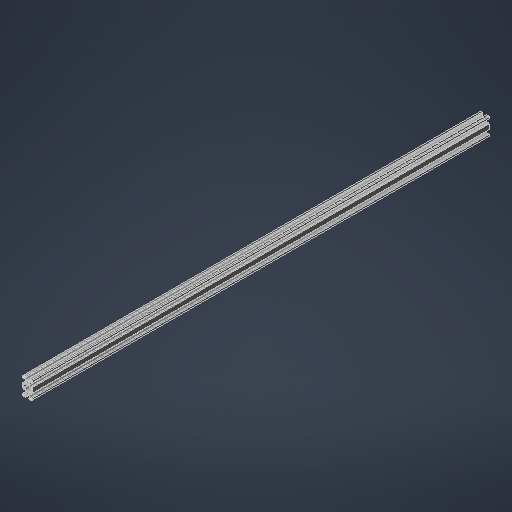
# Autodesk Inventor part: 2040aluminum_extrusion_black
Saved by Autodesk Inventor 2027.1 (Build 311270010, 270A)
## iProperties
Created: 2021-10-28
Part Number: 2040aluminum_extrusion_black
Material: Aluminum 6061
Document SubType Name: Modeling
Designer: casper
Density: 2.7 g/cm^3
Appearance: Satin - Black
Author: casper
Autodesk Inventor part; units mm, degrees
ref_plane "YZ Plane" through (0, 0, 0) normal (1, 0, 0) x (0, 1, 0)
ref_plane "XZ Plane" through (0, 0, 0) normal (0, 1, 0) x (-1, 0, 0)
sketch "Sketch1" plane through (0, 0, 0) normal (0, 0, 1) x (1, 0, 0)
  line L0 (0, 3.7) -> (-2.6393, 3.7)
  line L1 (-2.6393, 3.7) -> (-5.5, 6.5607)
  line L2 (-5.5, 6.5607) -> (-5.5, 8.2)
  line L3 (-5.5, 8.2) -> (-3.395, 8.2)
  line L4 (-3.395, 8.2) -> (-3.395, 10)
  line L5 (-3.395, 10) -> (-10, 10)
  line L6 (-10, 10) -> (-10, 3.395)
  line L7 (-10, 3.395) -> (-8.2, 3.395)
  line L8 (-8.2, 3.395) -> (-8.2, 5.5)
  line L9 (-8.2, 5.5) -> (-6.5607, 5.5)
  line L10 (-6.5607, 5.5) -> (-3.7, 2.6393)
  line L11 (-3.7, 2.6393) -> (-3.7, 0)
  line L12 (0, 0) -> (-10, 10) construction
  circle A0 centre (0, 0) radius 2.3
  line L13 (-22.6601, 0) -> (65.9605, 0) projected
  line L14 (-3.7, 0) -> (0, 0)
  line L15 (0, 0) -> (0, 3.7)
  line L16 (11.2521, 18.9743) -> (53.3004, 18.9743) construction
  line L17 (53.3004, 18.9743) -> (53.3004, -5.624) construction
  line L18 (53.3004, -5.624) -> (11.2521, -5.624) construction
  line L19 (11.2521, -5.624) -> (11.2521, 18.9743) construction
  point P0 (-2.3, 0)
  point P1 (0, 2.3)
  dimension "d0" = 1.5
  dimension "d6" = 6.3
  dimension "d9" = 4.6
  dimension "d18" = 135
  dimension "d22" = 20
  dimension "d34" = 11
  dimension "d35" = 6.79
  dimension "d36" = 1.8
  constraints: 30 end point, 6 equal length, 6 perpendicular, 2 horizontal, 2 parallel, 2 vertical, 1 centre point, 1 coincident, 2 other
  measures "d0" distance between parallel lines of L1 L10
  measures "d6" distance between parallel lines of L0 L5
  measures "d9" diameter of A0
  measures "d18" angle of L13 L12
  measures "d22" diameter of L5 L14
  measures "d34" diameter of L2 L15
  measures "d35" diameter of L4 L15
  measures "d36" distance between parallel lines of L5 L3
extrude "Extrusion1" add sketch "Sketch1" along normal mid plane 1000 contours L15 A0 L13 L11 L10 L9 L8 L7 L6 L5 L4 L3 L2 L1 L0
pattern_circular "Circular Pattern1" count 4 over 360 about axis through (0, 0, -10) along (0, 0, 1) of "Extrusion1"
chamfer "Chamfer1" distance 1.185 angle 45 8 edges at (-3.395, 10, 0) (3.395, 10, 0) (10, 3.395, 0) (10, -3.395, 0) (3.395, -10, 0) (-3.395, -10, 0) (-10, -3.395, 0) (-10, 3.395, 0)
ref_plane "Work Plane1" through (4.58, 10, 500) normal (0, 1, 0) x (1, 0, 0)
mirror "Mirror1" about plane through (4.58, 10, 500) normal (0, 1, 0)
sketch "Sketch2" plane through (0, 0, 500) normal (0, 0, 1) x (1, 0, 0)
  line L0 (-10, 4.58) -> (-10, 15.42) projected
  line L1 (-8.815, 3.395) -> (-10, 4.58) projected
  line L2 (-8.815, 3.395) -> (-8.2, 3.395) projected
  line L3 (-8.2, 3.395) -> (-8.2, 5.5) projected
  line L4 (-8.2, 5.5) -> (-6.5607, 5.5) projected
  line L5 (-6.5607, 5.5) -> (-3.7, 2.6393) projected
  line L6 (-3.7, 2.6393) -> (-3.7, 0) projected
  line L7 (-3.7, 0) -> (-3.7, -2.6393) projected
  line L8 (-3.7, -2.6393) -> (-6.5607, -5.5) projected
  line L9 (-6.5607, -5.5) -> (-8.2, -5.5) projected
  line L10 (-8.2, -5.5) -> (-8.2, -3.395) projected
  line L11 (-8.2, -3.395) -> (-8.815, -3.395) projected
  line L12 (-10, -4.58) -> (-8.815, -3.395) projected
  line L13 (-10, -4.58) -> (-10, -10) projected
  line L14 (-10, -10) -> (-4.58, -10) projected
  line L15 (-3.395, -8.815) -> (-4.58, -10) projected
  line L16 (-3.395, -8.815) -> (-3.395, -8.2) projected
  line L17 (-3.395, -8.2) -> (-5.5, -8.2) projected
  line L18 (-5.5, -8.2) -> (-5.5, -6.5607) projected
  line L19 (-5.5, -6.5607) -> (-2.6393, -3.7) projected
  line L20 (-2.6393, -3.7) -> (0, -3.7) projected
  line L21 (0, -3.7) -> (2.6393, -3.7) projected
  line L22 (2.6393, -3.7) -> (5.5, -6.5607) projected
  line L23 (5.5, -6.5607) -> (5.5, -8.2) projected
  line L24 (5.5, -8.2) -> (3.395, -8.2) projected
  line L25 (3.395, -8.2) -> (3.395, -8.815) projected
  line L26 (4.58, -10) -> (3.395, -8.815) projected
  line L27 (4.58, -10) -> (10, -10) projected
  line L28 (10, -10) -> (10, -4.58) projected
  line L29 (8.815, -3.395) -> (10, -4.58) projected
  line L30 (8.815, -3.395) -> (8.2, -3.395) projected
  line L31 (8.2, -3.395) -> (8.2, -5.5) projected
  line L32 (8.2, -5.5) -> (6.5607, -5.5) projected
  line L33 (6.5607, -5.5) -> (3.7, -2.6393) projected
  line L34 (3.7, -2.6393) -> (3.7, 0) projected
  line L35 (3.7, 0) -> (3.7, 2.6393) projected
  line L36 (3.7, 2.6393) -> (6.5607, 5.5) projected
  line L37 (6.5607, 5.5) -> (8.2, 5.5) projected
  line L38 (8.2, 5.5) -> (8.2, 3.395) projected
  line L39 (8.2, 3.395) -> (8.815, 3.395) projected
  line L40 (10, 4.58) -> (8.815, 3.395) projected
  line L41 (10, 4.58) -> (10, 15.42) projected
  line L42 (10, 15.42) -> (8.815, 16.605) projected
  line L43 (8.2, 16.605) -> (8.815, 16.605) projected
  line L44 (8.2, 14.5) -> (8.2, 16.605) projected
  line L45 (6.5607, 14.5) -> (8.2, 14.5) projected
  line L46 (3.7, 17.3607) -> (6.5607, 14.5) projected
  line L47 (3.7, 20) -> (3.7, 17.3607) projected
  line L48 (3.7, 22.6393) -> (3.7, 20) projected
  line L49 (6.5607, 25.5) -> (3.7, 22.6393) projected
  line L50 (8.2, 25.5) -> (6.5607, 25.5) projected
  line L51 (8.2, 23.395) -> (8.2, 25.5) projected
  line L52 (8.815, 23.395) -> (8.2, 23.395) projected
  line L53 (8.815, 23.395) -> (10, 24.58) projected
  line L54 (10, 30) -> (10, 24.58) projected
  line L55 (4.58, 30) -> (10, 30) projected
  line L56 (4.58, 30) -> (3.395, 28.815) projected
  line L57 (3.395, 28.2) -> (3.395, 28.815) projected
  line L58 (5.5, 28.2) -> (3.395, 28.2) projected
  line L59 (5.5, 26.5607) -> (5.5, 28.2) projected
  line L60 (2.6393, 23.7) -> (5.5, 26.5607) projected
  line L61 (0, 23.7) -> (2.6393, 23.7) projected
  line L62 (-2.6393, 23.7) -> (0, 23.7) projected
  line L63 (-5.5, 26.5607) -> (-2.6393, 23.7) projected
  line L64 (-5.5, 28.2) -> (-5.5, 26.5607) projected
  line L65 (-3.395, 28.2) -> (-5.5, 28.2) projected
  line L66 (-3.395, 28.815) -> (-3.395, 28.2) projected
  line L67 (-3.395, 28.815) -> (-4.58, 30) projected
  line L68 (-10, 30) -> (-4.58, 30) projected
  line L69 (-10, 24.58) -> (-10, 30) projected
  line L70 (-10, 24.58) -> (-8.815, 23.395) projected
  line L71 (-8.2, 23.395) -> (-8.815, 23.395) projected
  line L72 (-8.2, 25.5) -> (-8.2, 23.395) projected
  line L73 (-6.5607, 25.5) -> (-8.2, 25.5) projected
  line L74 (-3.7, 22.6393) -> (-6.5607, 25.5) projected
  line L75 (-3.7, 20) -> (-3.7, 22.6393) projected
  line L76 (-3.7, 17.3607) -> (-3.7, 20) projected
  line L77 (-6.5607, 14.5) -> (-3.7, 17.3607) projected
  line L78 (-8.2, 14.5) -> (-6.5607, 14.5) projected
  line L79 (-8.2, 16.605) -> (-8.2, 14.5) projected
  line L80 (-8.815, 16.605) -> (-8.2, 16.605) projected
  line L81 (-8.815, 16.605) -> (-10, 15.42) projected
  circle A0 centre (0, 20) radius 2.3 projected
  line L82 (-4.58, 10) -> (-3.395, 11.185) projected
  line L83 (-3.395, 11.8) -> (-3.395, 11.185) projected
  line L84 (-5.5, 11.8) -> (-3.395, 11.8) projected
  line L85 (-5.5, 13.4393) -> (-5.5, 11.8) projected
  line L86 (-2.6393, 16.3) -> (-5.5, 13.4393) projected
  line L87 (0, 16.3) -> (-2.6393, 16.3) projected
  line L88 (2.6393, 16.3) -> (0, 16.3) projected
  line L89 (5.5, 13.4393) -> (2.6393, 16.3) projected
  line L90 (5.5, 11.8) -> (5.5, 13.4393) projected
  line L91 (3.395, 11.8) -> (5.5, 11.8) projected
  line L92 (3.395, 11.185) -> (3.395, 11.8) projected
  line L93 (3.395, 11.185) -> (4.58, 10) projected
  line L94 (3.395, 8.815) -> (4.58, 10) projected
  line L95 (3.395, 8.815) -> (3.395, 8.2) projected
  line L96 (3.395, 8.2) -> (5.5, 8.2) projected
  line L97 (5.5, 8.2) -> (5.5, 6.5607) projected
  line L98 (5.5, 6.5607) -> (2.6393, 3.7) projected
  line L99 (2.6393, 3.7) -> (0, 3.7) projected
  line L100 (0, 3.7) -> (-2.6393, 3.7) projected
  line L101 (-2.6393, 3.7) -> (-5.5, 6.5607) projected
  line L102 (-5.5, 6.5607) -> (-5.5, 8.2) projected
  line L103 (-5.5, 8.2) -> (-3.395, 8.2) projected
  line L104 (-3.395, 8.2) -> (-3.395, 8.815) projected
  line L105 (-4.58, 10) -> (-3.395, 8.815) projected
  circle A1 centre (0, 0) radius 2.3 projected
  line L106 (-5.5, 8.2) -> (-5.5, 6.5607) projected
  line L107 (-5.5, 6.5607) -> (-6.2393, 7.3)
  line L108 (-5.5, 6.5607) -> (-2.6393, 3.7) projected
  line L109 (-6.2393, 7.3) -> (-8.2, 7.3)
  line L110 (-8.2, 7.3) -> (-8.2, 12.7)
  line L111 (-8.2, 12.7) -> (-6.2393, 12.7)
  line L112 (-6.2393, 12.7) -> (-5.5, 13.4393)
  line L113 (-2.6393, 16.3) -> (-5.5, 13.4393) projected
  line L114 (-8.2, 16.605) -> (-8.2, 14.5) projected
  dimension "d42" = 1.8
  constraints: 10 end point, 3 collinear, 2 perpendicular, 1 horizontal, 1 vertical alignment
  measures "d42" distance between parallel lines of L4 L109
extrude "Extrusion2" cut sketch "Sketch2" against normal through all contours L105 L104 L103 L102 L107 L109 L110 L111 L112 L85 L84 L83 L82
fillet "Fillet2" radius 1.5 4 edges at (-10, 30, 0) (10, 30, 0) (10, -10, 0) (-10, -10, 0)
mirror "Mirror2" about plane through (0, 0, 0) normal (1, 0, 0) of "Extrusion2"
equation "\"GridProcutClearance\" = 3"
equation "\"GridBorderThickness\" = 5"
equation "\"GridBorderFillets\" = 7"
equation "\"GridTotalSize\" = 63"
equation "\"BaseTotalWidth\" = 412"
equation "\"BaseTotalLength\" = 624"
equation "\"DistanceBetweenGrid\" = 5"
equation "\"WorkspaceLength\" = 395"
equation "\"WorkspaceWidth\" = 332"
equation "\"AxesBaseFillet\" = 15"
equation "\"Zaxis\" = 127"
body "Solid1"
